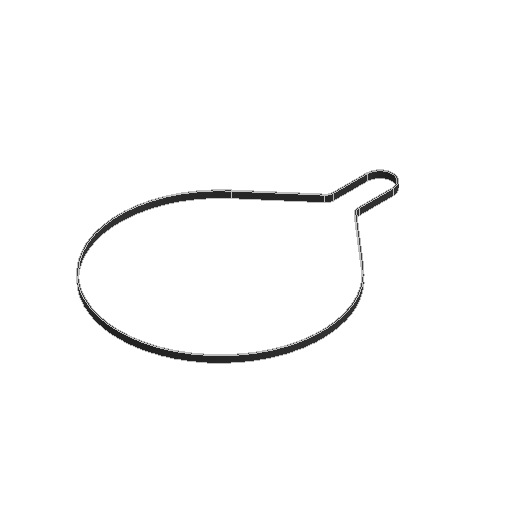
# Autodesk Inventor part: COTS_GENERIC_HTD3M_6mm_675mm_Closed_belt_A_Axis
Saved by Autodesk Inventor 2027 (Build 310192060, 192F)
## iProperties
Created: 2026-01-06
Part Number: COTS_GENERIC_HTD3M_6mm_675mm_Closed_belt_A_Axis
Material: Generic
Document SubType Name: Modeling
Designer: User
Density: 1 g/cm^3
Appearance: Rubber - Black
Author: User
Autodesk Inventor part; units mm, degrees
ref_plane "YZ Plane" through (0, 0, 0) normal (1, 0, 0) x (0, 1, 0)
ref_plane "XZ Plane" through (0, 0, 0) normal (0, 1, 0) x (-1, 0, 0)
ref_plane "XY Plane" through (0, 0, 0) normal (0, 0, 1) x (1, 0, 0)
sketch "Sketch1" plane through (0, 0, 0) normal (0, 1, 0) x (-1, 0, 0)
  arc A0 (-11.075, -145) -> (11.075, -145) centre (0, -145) ccw
  arc A1 (59.4432, -69.2847) -> (-59.4432, -69.2847) centre (0, 0) ccw
  arc A2 (13.517, -108.6873) -> (11.075, -114) centre (18.075, -114) ccw
  arc A3 (-11.075, -114) -> (-13.517, -108.6873) centre (-18.075, -114) ccw
  line L0 (11.075, -145) -> (11.075, -114)
  line L1 (-11.075, -145) -> (-11.075, -114)
  line L2 (-13.517, -108.6873) -> (-59.4432, -69.2847)
  line L3 (13.517, -108.6873) -> (59.4432, -69.2847)
  line L4 (-60.2245, -70.1955) -> (-14.2983, -109.5981)
  arc A4 (-12.275, -114) -> (-14.2983, -109.5981) centre (-18.075, -114) ccw
  line L5 (-12.275, -114) -> (-12.275, -145)
  arc A5 (-12.275, -145) -> (12.275, -145) centre (0, -145) ccw
  line L6 (12.275, -145) -> (12.275, -114)
  arc A6 (14.2983, -109.5981) -> (12.275, -114) centre (18.075, -114) ccw
  line L7 (14.2983, -109.5981) -> (60.2245, -70.1955)
  arc A7 (60.2245, -70.1955) -> (-60.2245, -70.1955) centre (0, 0) ccw
  dimension "d0" = 22.15
  dimension "d1" = 145
  dimension "d2" = 182.58
  dimension "d3" = 14
  dimension "d4" = 18.075
  dimension "d5" = 114
  dimension "d6" = 14
  dimension "d7" = 18.075
  dimension "d8" = 1.2
  constraints: 16 end point, 16 point on circle, 8 centre point, 6 tangent, 1 coincident, 1 horizontal alignment, 7 other
  measures "d0" diameter of A0
  measures "d1" distance of A0.centre point (0, 0)
  measures "d2" diameter of A1
  measures "d3" diameter of A2
  measures "d4" horizontal distance of point (0, 0) A2.centre
  measures "d5" vertical distance of point (0, 0) A2.centre
  measures "d6" diameter of A3
  measures "d7" horizontal distance of A3.centre point (0, 0)
  measures "d8" radial gap between concentric circles of A1 A7
extrude "Extrusion1" add sketch "Sketch1" along normal blind 6
equation "\"d7\" = d4"
body "Solid1"
